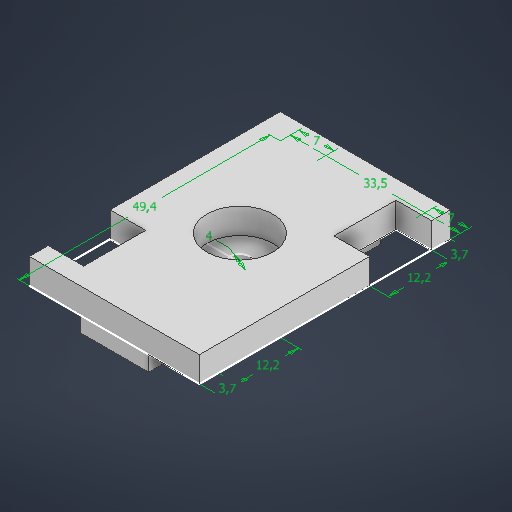
# Autodesk Inventor part: motorsuperior
Saved by Autodesk Inventor 2026.2 (Build 302298010, 298A)
## iProperties
Created: 2026-08-23
Part Number: motorsuperior
Material: Genérico
Document SubType Name: Sheet Metal
Designer: Admin
Density: 1 g/cm^3
Sheet Metal Rule: Padrão_mm
Appearance: Padrão
Author: Admin
Autodesk Inventor part; units mm, degrees
ref_plane "YZ Plane" through (0, 0, 0) normal (1, 0, 0) x (0, 1, 0)
ref_plane "XZ Plane" through (0, 0, 0) normal (0, 1, 0) x (-1, 0, 0)
ref_plane "XY Plane" through (0, 0, 0) normal (0, 0, 1) x (1, 0, 0)
sketch "Esboço1" plane through (0, 0, 0) normal (0, 1, 0) x (-1, 0, 0)
  line L0 (0, 0) -> (33.5, 0)
  line L1 (33.5, 0) -> (33.5, -49.4)
  line L2 (33.5, -49.4) -> (0, -49.4)
  line L3 (0, -49.4) -> (0, 0)
  line L4 (33.5, 0) -> (26.5, 0)
  line L5 (26.5, 0) -> (26.5, -49.4)
  line L6 (26.5, -49.4) -> (33.5, -49.4)
  line L7 (33.5, -49.4) -> (33.5, 0)
  line L8 (0, 0) -> (7, 0)
  line L9 (7, 0) -> (7, -49.4)
  line L10 (7, -49.4) -> (0, -49.4)
  line L11 (0, -49.4) -> (0, 0)
  line L12 (33.5, -49.4) -> (0, -49.4)
  line L13 (0, -49.4) -> (0, -45.7)
  line L14 (0, -45.7) -> (33.5, -45.7)
  line L15 (33.5, -45.7) -> (33.5, -49.4)
  line L16 (33.5, 0) -> (0, 0)
  line L17 (0, 0) -> (0, -3.7)
  line L18 (0, -3.7) -> (33.5, -3.7)
  line L19 (33.5, -3.7) -> (33.5, 0)
  line L20 (33.5, -3.7) -> (0, -3.7)
  line L21 (0, -3.7) -> (0, -15.9)
  line L22 (0, -15.9) -> (33.5, -15.9)
  line L23 (33.5, -15.9) -> (33.5, -3.7)
  line L24 (33.5, -45.7) -> (0, -45.7)
  line L25 (0, -45.7) -> (0, -33.5)
  line L26 (0, -33.5) -> (33.5, -33.5)
  line L27 (33.5, -33.5) -> (33.5, -45.7)
  line L28 (0, -24.7) -> (33.5, -24.7)
  circle A0 centre (16.75, -24.7) radius 2
  point P0 (26.5, -45.7)
  point P1 (7, -45.7)
  point P2 (26.5, -15.9)
  point P3 (7, -15.9)
  point P4 (7, -33.5)
  point P5 (26.5, -33.5)
  point P6 (7, -3.7)
  point P7 (26.5, -3.7)
  dimension "d0" = 33.5
  dimension "d1" = 49.4
  dimension "d2" = 7
  dimension "d3" = 7
  dimension "d4" = 3.7
  dimension "d5" = 3.7
  dimension "d6" = 12.2
  dimension "d7" = 12.2
  dimension "d8" = 4
  constraints: 58 end point, 14 parallel, 7 horizontal, 7 perpendicular, 6 point on line, 3 midpoint, 1 centre point
  measures "d0" distance of L1.end L2.end
  measures "d1" distance of L0.end L1.end
  measures "d2" distance of L6.end L5.end
  measures "d3" distance of L9.end L10.end
  measures "d4" distance of L12.end L13.end
  measures "d5" distance of L17.end L16.end
  measures "d6" distance of L21.end L20.end
  measures "d7" distance of L24.end L25.end
  measures "d8" diameter of A0
extrude "Extrusão1" add sketch "Esboço1" along normal blind 5 contours L0 L9 L18 L3 | L0 L5 L18 L9 | L18 L9 L22 L3 | L0 L1 L18 L5 | L18 L5 L22 L9 | L22 L9 L28 L3 | L18 L1 L22 L5 | L22 L5 L28 A0 L9 | L28 L9 L26 L3 | L22 L1 L28 L5 | L28 A0 L5 L26 L9 | L26 L9 L14 L3 | L28 L1 L26 L5 | L26 L5 L14 L9 | L14 L9 L2 L3 | L26 L1 L14 L5 | L14 L5 L2 L9 | L14 L1 L2 L5
extrude "Extrusão2" add sketch "Esboço1" against normal blind 3 contours L0 L5 L18 L9 | L22 L5 L28 A0 L9 | L28 A0 L5 L26 L9 | L14 L5 L2 L9
extrude "Extrusão3" add sketch "Esboço1" against normal blind 4 contours L18 L5 L22 L9 | L26 L5 L14 L9
extrude "Extrusão4" cut sketch "Esboço1" along normal blind 10 contours L18 L1 L22 L5 | L26 L9 L14 L3
sketch "Esboço2" plane through (0, 5, 0) normal (0, 1, 0) x (1, 0, 0)
  circle A0 centre (-16.75, 24.7) radius 2 projected
  circle A1 centre (-16.75, 24.7) radius 5
  circle A2 centre (-16.75, 24.7) radius 7.5
  circle A3 centre (-16.75, 24.7) radius 6.5
  point P0 (0, 0)
  dimension "d17" = 10
  dimension "d24" = 15
  dimension "d25" = 13
  constraints: 3 centre point, 3 coincident
  measures "d17" diameter of A1
  measures "d24" diameter of A2
  measures "d25" diameter of A3
extrude "Extrusão5" cut sketch "Esboço2" against normal blind 5 contours A0 | A1 | A3
sketch "Esboço3" plane through (0, -4, 0) normal (0, -1, 0) x (1, 0, 0)
  line L0 (-7, -3.7) -> (-26.5, -3.7) projected
  line L1 (0, -49.4) -> (-33.5, -49.4) projected
  line L2 (-26.5, -3.7) -> (-23.5, -3.7)
  line L3 (-23.5, -3.7) -> (-23.5, -49.4)
  line L4 (-23.5, -49.4) -> (-26.5, -49.4)
  line L5 (-26.5, -49.4) -> (-26.5, -3.7)
  line L6 (-7, -49.4) -> (-10, -49.4)
  line L7 (-10, -49.4) -> (-10, -3.7)
  line L8 (-10, -3.7) -> (-7, -3.7)
  line L9 (-7, -3.7) -> (-7, -49.4)
  line L10 (-33.5, 0) -> (0, 0) projected
  line L11 (-26.5, -3.7) -> (-23.5, -3.7)
  line L12 (-23.5, -3.7) -> (-23.5, 0)
  line L13 (-23.5, 0) -> (-26.5, 0)
  line L14 (-26.5, 0) -> (-26.5, -3.7)
  line L15 (-10, -3.7) -> (-7, -3.7)
  line L16 (-7, -3.7) -> (-7, 0)
  line L17 (-7, 0) -> (-10, 0)
  line L18 (-10, 0) -> (-10, -3.7)
  dimension "d20" = 3
  dimension "d21" = 3
  constraints: 32 end point, 8 parallel, 5 point on line, 4 horizontal, 4 perpendicular
  measures "d20" distance of L3.end L4.end
  measures "d21" distance of L7.end L8.end
extrude "Extrusão6" cut sketch "Esboço3" against normal blind 4 contours L9 L1 L7 L0 | L0 L18 L10 L16 | L3 L1 L5 L0 | L0 L14 L10 L12
equation "\"Raio_vergadura\" = Espessura"
equation "\"Largura_alívio_de_vergadura\" = Espessura"
equation "\"Profundidade_alívio_de_vergadura\" = 0.5 * Espessura"
equation "\"Tamanho_alívio_de_dobra\" = 4 * Espessura"
equation "\"Remanescente_mínimo\" = 2 * Espessura"
equation "\"Raiodetransição\" = Raio_vergadura"
equation "\"Tamanho_de_raio_de_Jacobi\" = Raio_vergadura"
equation "\"TamanhoFolga\" = Espessura"
equation "\"Espessura\" = 0.5"
